Autodesk Fusion 360 part; units mm, degrees
(part 2 of 8)
extrude "Diffuser open rear skirt" add sketch "Diffuser hollow skirt outside profile" against normal blind 2.6 bodies 4
ref_plane "WorkPlane13" through (12.125, -2.4482, 27.9828) normal (0, -0.087156, 0.996195) x (1, 0, 0)
sketch "Diffuser optical cavity profile" plane through (0, -2.4482, 27.9828) normal (0, -0.087156, 0.996195) x (1, 0, 0)
  line L0 (7.7, 94.1972) -> (72.3, 94.1972)
  line L1 (72.3, 94.1972) -> (72.3, 101.7972)
  line L2 (72.3, 101.7972) -> (7.7, 101.7972)
  line L3 (7.7, 101.7972) -> (7.7, 94.1972)
  dimension "d533" = 7.7
  dimension "d534" = 94.1972
  dimension "d535" = 64.6
  dimension "d536" = 7.6
  constraint horizontal L0
  constraint vertical L1
  constraint horizontal L2
  constraint vertical L3
  measures "d533" horizontal distance of origin L0.start
  measures "d534" vertical distance of origin L0.start
  measures "d535" distance of L0.start L0.end
  measures "d536" distance of L0.end L1.end
extrude "Hollow diffuser from inside" cut sketch "Diffuser optical cavity profile" against normal blind 7 bodies 4
sketch "Diffuser right wire exit profile" plane through (0, -2.2216, 25.3927) normal (0, -0.087156, 0.996195) x (1, 0, 0)
  line L0 (71.5, 95.9972) -> (76.5, 95.9972)
  line L1 (76.5, 95.9972) -> (76.5, 99.9972)
  line L2 (76.5, 99.9972) -> (71.5, 99.9972)
  line L3 (71.5, 99.9972) -> (71.5, 95.9972)
  dimension "d539" = 71.5
  dimension "d540" = 95.9972
  dimension "d541" = 5
  dimension "d542" = 4
  constraint horizontal L0
  constraint vertical L1
  constraint horizontal L2
  constraint vertical L3
  measures "d539" horizontal distance of origin L0.start
  measures "d540" vertical distance of origin L0.start
  measures "d541" distance of L0.start L0.end
  measures "d542" distance of L0.end L1.end
extrude "Diffuser right wire exit" cut sketch "Diffuser right wire exit profile" against normal blind 6 bodies 4
sketch "Deep diffuser skirt clearance profile" plane through (0, -2.2739, 25.9904) normal (0, -0.087156, 0.996195) x (1, 0, 0)
  line L0 (5, 91.4972) -> (75, 91.4972)
  line L1 (75, 91.4972) -> (75, 104.4972)
  line L2 (75, 104.4972) -> (5, 104.4972)
  line L3 (5, 104.4972) -> (5, 91.4972)
  dimension "d545" = 5
  dimension "d546" = 91.4972
  dimension "d547" = 70
  dimension "d548" = 13
  constraint horizontal L0
  constraint vertical L1
  constraint horizontal L2
  constraint vertical L3
  measures "d545" horizontal distance of origin L0.start
  measures "d546" vertical distance of origin L0.start
  measures "d547" distance of L0.start L0.end
  measures "d548" distance of L0.end L1.end
extrude "Clear carrier around hollow diffuser" cut sketch "Deep diffuser skirt clearance profile" against normal blind 3.4 bodies 2
sketch "LED rear support web profile" plane through (0, -2.2739, 25.9904) normal (0, -0.087156, 0.996195) x (1, 0, 0)
  line L0 (6.3, 108.1799) -> (73.7, 108.1799)
  line L1 (73.7, 108.1799) -> (73.7, 112.1799)
  line L2 (73.7, 112.1799) -> (6.3, 112.1799)
  line L3 (6.3, 112.1799) -> (6.3, 108.1799)
  dimension "d551" = 6.3
  dimension "d552" = 108.1799
  dimension "d553" = 67.4
  dimension "d554" = 4
  constraint horizontal L0
  constraint vertical L1
  constraint horizontal L2
  constraint vertical L3
  measures "d551" horizontal distance of origin L0.start
  measures "d552" vertical distance of origin L0.start
  measures "d553" distance of L0.start L0.end
  measures "d554" distance of L0.end L1.end
extrude "LED rear support web" add sketch "LED rear support web profile" against normal blind 5.8 bodies 2
ref_plane "WorkPlane14" through (12.125, -1.9775, 22.6033) normal (0, -0.087156, 0.996195) x (1, 0, 0)
sketch "Continuous LED tray profile" plane through (0, -1.9775, 22.6033) normal (0, -0.087156, 0.996195) x (1, 0, 0)
  line L0 (6.3, 92.7972) -> (73.7, 92.7972)
  line L1 (73.7, 92.7972) -> (73.7, 114.4037)
  line L2 (73.7, 114.4037) -> (6.3, 114.4037)
  line L3 (6.3, 114.4037) -> (6.3, 92.7972)
  dimension "d559" = 6.3
  dimension "d560" = 92.7972
  dimension "d561" = 67.4
  dimension "d562" = 21.6065
  constraint horizontal L0
  constraint vertical L1
  constraint horizontal L2
  constraint vertical L3
  measures "d559" horizontal distance of origin L0.start
  measures "d560" vertical distance of origin L0.start
  measures "d561" distance of L0.start L0.end
  measures "d562" distance of L0.end L1.end
extrude "Continuous LED mounting crossbar" add sketch "Continuous LED tray profile" against normal blind 2.4 bodies 2
sketch "LED tray right wire relief profile" plane through (0, -1.9775, 22.6033) normal (0, -0.087156, 0.996195) x (1, 0, 0)
  line L0 (71.5, 95.9972) -> (75.5, 95.9972)
  line L1 (75.5, 95.9972) -> (75.5, 99.9972)
  line L2 (75.5, 99.9972) -> (71.5, 99.9972)
  line L3 (71.5, 99.9972) -> (71.5, 95.9972)
  dimension "d565" = 71.5
  dimension "d566" = 95.9972
  dimension "d567" = 4
  dimension "d568" = 4
  constraint horizontal L0
  constraint vertical L1
  constraint horizontal L2
  constraint vertical L3
  measures "d565" horizontal distance of origin L0.start
  measures "d566" vertical distance of origin L0.start
  measures "d567" distance of L0.start L0.end
  measures "d568" distance of L0.end L1.end
extrude "LED tray right wire relief" cut sketch "LED tray right wire relief profile" against normal blind 3.4 bodies 2
sketch "OLED seat 1 profile" plane through (0, -2.5179, 28.7797) normal (0, -0.087156, 0.996195) x (1, 0, 0)
  line L0 (5.75, 59.4972) -> (41.75, 59.4972)
  line L1 (41.75, 59.4972) -> (41.75, 62.4972)
  line L2 (41.75, 62.4972) -> (5.75, 62.4972)
  line L3 (5.75, 62.4972) -> (5.75, 59.4972)
  dimension "d571" = 5.75
  dimension "d572" = 59.4972
  dimension "d573" = 36
  dimension "d574" = 3
  constraint horizontal L0
  constraint vertical L1
  constraint horizontal L2
  constraint vertical L3
  measures "d571" horizontal distance of origin L0.start
  measures "d572" vertical distance of origin L0.start
  measures "d573" distance of L0.start L0.end
  measures "d574" distance of L0.end L1.end
extrude "OLED opposed locating ledge 1" add sketch "OLED seat 1 profile" against normal blind 2.8 bodies 1
sketch "OLED seat 2 profile" plane through (0, -2.5179, 28.7797) normal (0, -0.087156, 0.996195) x (1, 0, 0)
  line L0 (5.75, 88.4972) -> (41.75, 88.4972)
  line L1 (41.75, 88.4972) -> (41.75, 91.4972)
  line L2 (41.75, 91.4972) -> (5.75, 91.4972)
  line L3 (5.75, 91.4972) -> (5.75, 88.4972)
  dimension "d577" = 5.75
  dimension "d578" = 88.4972
  dimension "d579" = 36
  dimension "d580" = 3
  constraint horizontal L0
  constraint vertical L1
  constraint horizontal L2
  constraint vertical L3
  measures "d577" horizontal distance of origin L0.start
  measures "d578" vertical distance of origin L0.start
  measures "d579" distance of L0.start L0.end
  measures "d580" distance of L0.end L1.end
extrude "OLED opposed locating ledge 2" add sketch "OLED seat 2 profile" against normal blind 2.8 bodies 1
sketch "OLED PCB carrier clearance profile" plane through (0, -2.2739, 25.9904) normal (0, -0.087156, 0.996195) x (1, 0, 0)
  line L0 (5.55, 59.2972) -> (41.95, 59.2972)
  line L1 (41.95, 59.2972) -> (41.95, 93.6972)
  line L2 (41.95, 93.6972) -> (5.55, 93.6972)
  line L3 (5.55, 93.6972) -> (5.55, 59.2972)
  dimension "d583" = 5.55
  dimension "d584" = 59.2972
  dimension "d585" = 36.4
  dimension "d586" = 34.4
  constraint horizontal L0
  constraint vertical L1
  constraint horizontal L2
  constraint vertical L3
  measures "d583" horizontal distance of origin L0.start
  measures "d584" vertical distance of origin L0.start
  measures "d585" distance of L0.start L0.end
  measures "d586" distance of L0.end L1.end
extrude "OLED PCB clearance in carrier" cut sketch "OLED PCB carrier clearance profile" against normal blind 1.8 bodies 2
ref_plane "WorkPlane15" through (12.125, -2.117, 24.1972) normal (0, -0.087156, 0.996195) x (1, 0, 0)
sketch "OLED front clamp root profile" plane through (0, -2.2739, 25.9904) normal (0, -0.087156, 0.996195) x (1, 0, 0)
  line L0 (18, 58.4972) -> (32, 58.4972)
  line L1 (32, 58.4972) -> (32, 59.4972)
  line L2 (32, 59.4972) -> (18, 59.4972)
  line L3 (18, 59.4972) -> (18, 58.4972)
  dimension "d591" = 18
  dimension "d592" = 58.4972
  dimension "d593" = 14
  dimension "d594" = 1
  constraint horizontal L0
  constraint vertical L1
  constraint horizontal L2
  constraint vertical L3
  measures "d591" horizontal distance of origin L0.start
  measures "d592" vertical distance of origin L0.start
  measures "d593" distance of L0.start L0.end
  measures "d594" distance of L0.end L1.end
extrude "OLED front clamp root" add sketch "OLED front clamp root profile" against normal blind 3.8 bodies 2
sketch "OLED front opposed clamp profile" plane through (0, -2.117, 24.1972) normal (0, -0.087156, 0.996195) x (1, 0, 0)
  line L0 (18, 58.4972) -> (32, 58.4972)
  line L1 (32, 58.4972) -> (32, 62.4972)
  line L2 (32, 62.4972) -> (18, 62.4972)
  line L3 (18, 62.4972) -> (18, 58.4972)
  dimension "d597" = 18
  dimension "d598" = 58.4972
  dimension "d599" = 14
  dimension "d600" = 4
  constraint horizontal L0
  constraint vertical L1
  constraint horizontal L2
  constraint vertical L3
  measures "d597" horizontal distance of origin L0.start
  measures "d598" vertical distance of origin L0.start
  measures "d599" distance of L0.start L0.end
  measures "d600" distance of L0.end L1.end
extrude "OLED front opposed clamp" add sketch "OLED front opposed clamp profile" against normal blind 2 bodies 2
sketch "OLED rear clamp connecting bridge profile" plane through (0, -1.9775, 22.6033) normal (0, -0.087156, 0.996195) x (1, 0, 0)
  line L0 (18, 89.2972) -> (32, 89.2972)
  line L1 (32, 89.2972) -> (32, 93.0972)
  line L2 (32, 93.0972) -> (18, 93.0972)
  line L3 (18, 93.0972) -> (18, 89.2972)
  dimension "d603" = 18
  dimension "d604" = 89.2972
  dimension "d605" = 14
  dimension "d606" = 3.8
  constraint horizontal L0
  constraint vertical L1
  constraint horizontal L2
  constraint vertical L3
  measures "d603" horizontal distance of origin L0.start
  measures "d604" vertical distance of origin L0.start
  measures "d605" distance of L0.start L0.end
  measures "d606" distance of L0.end L1.end
extrude "OLED rear clamp connecting bridge" add sketch "OLED rear clamp connecting bridge profile" against normal blind 2.4 bodies 2
sketch "OLED rear opposed clamp profile" plane through (0, -2.117, 24.1972) normal (0, -0.087156, 0.996195) x (1, 0, 0)
  line L0 (18, 89.4972) -> (32, 89.4972)
  line L1 (32, 89.4972) -> (32, 91.4972)
  line L2 (32, 91.4972) -> (18, 91.4972)
  line L3 (18, 91.4972) -> (18, 89.4972)
  dimension "d609" = 18
  dimension "d610" = 89.4972
  dimension "d611" = 14
  dimension "d612" = 2
  constraint horizontal L0
  constraint vertical L1
  constraint horizontal L2
  constraint vertical L3
  measures "d609" horizontal distance of origin L0.start
  measures "d610" vertical distance of origin L0.start
  measures "d611" distance of L0.start L0.end
  measures "d612" distance of L0.end L1.end
extrude "OLED rear opposed clamp" add sketch "OLED rear opposed clamp profile" against normal blind 2 bodies 2
sketch "OLED PCB carrier clearance profile (1)" plane through (0, -2.2739, 25.9904) normal (0, -0.087156, 0.996195) x (1, 0, 0)
  line L0 (5.55, 59.2972) -> (41.95, 59.2972)
  line L1 (41.95, 59.2972) -> (41.95, 93.6972)
  line L2 (41.95, 93.6972) -> (5.55, 93.6972)
  line L3 (5.55, 93.6972) -> (5.55, 59.2972)
  dimension "d615" = 5.55
  dimension "d616" = 59.2972
  dimension "d617" = 36.4
  dimension "d618" = 34.4
  constraint horizontal L0
  constraint vertical L1
  constraint horizontal L2
  constraint vertical L3
  measures "d615" horizontal distance of origin L0.start
  measures "d616" vertical distance of origin L0.start
  measures "d617" distance of L0.start L0.end
  measures "d618" distance of L0.end L1.end
extrude "OLED PCB clearance in carrier (1)" cut sketch "OLED PCB carrier clearance profile (1)" against normal blind 1.8 bodies 2
ref_plane "WorkPlane16" through (0, 0, 26.3) normal (0, 0, 1) x (1, 0, 0)
sketch "PCB1 perimeter support profile" plane through (0, 0, 26.3) normal (0, 0, 1) x (1, 0, 0)
  line L0 (3.2, 62.2) -> (4.8, 62.2)
  line L1 (4.8, 62.2) -> (4.8, 66.2)
  line L2 (4.8, 66.2) -> (3.2, 66.2)
  line L3 (3.2, 66.2) -> (3.2, 62.2)
  dimension "d623" = 3.2
  dimension "d624" = 62.2
  dimension "d625" = 1.6
  dimension "d626" = 4
  constraint horizontal L0
  constraint vertical L1
  constraint horizontal L2
  constraint vertical L3
  measures "d623" horizontal distance of origin L0.start
  measures "d624" vertical distance of origin L0.start
  measures "d625" distance of L0.start L0.end
  measures "d626" distance of L0.end L1.end
sketch "PCB1 short post bridge profile" plane through (0, 0, 26.3) normal (0, 0, 1) x (1, 0, 0)
  line L0 (3.2, 62.2) -> (7, 62.2)
  line L1 (7, 62.2) -> (7, 66.2)
  line L2 (7, 66.2) -> (3.2, 66.2)
  line L3 (3.2, 66.2) -> (3.2, 62.2)
  dimension "d629" = 3.2
  dimension "d630" = 62.2
  dimension "d631" = 3.8
  dimension "d632" = 4
  constraint horizontal L0
  constraint vertical L1
  constraint horizontal L2
  constraint vertical L3
  measures "d629" horizontal distance of origin L0.start
  measures "d630" vertical distance of origin L0.start
  measures "d631" distance of L0.start L0.end
  measures "d632" distance of L0.end L1.end
sketch "PCB1 post profile" plane through (0, 0, 22.3) normal (0, 0, 1) x (1, 0, 0)
  circle A0 centre (7, 64.2) radius 2.2
  dimension "d635" = 7
  dimension "d636" = 64.2
  dimension "d637" = 4.4
  measures "d635" horizontal distance of origin A0.centre
  measures "d636" vertical distance of origin A0.centre
  measures "d637" diameter of A0
sketch "PCB1 M2 pilot profile" plane through (0, 0, 22.3) normal (0, 0, 1) x (1, 0, 0)
  circle A0 centre (7, 64.2) radius 0.85
  dimension "d640" = 7
  dimension "d641" = 64.2
  dimension "d642" = 1.7
  measures "d640" horizontal distance of origin A0.centre
  measures "d641" vertical distance of origin A0.centre
  measures "d642" diameter of A0
sketch "PCB2 perimeter support profile" plane through (0, 0, 26.3) normal (0, 0, 1) x (1, 0, 0)
  line L0 (75.2, 62.2) -> (76.8, 62.2)
  line L1 (76.8, 62.2) -> (76.8, 66.2)
  line L2 (76.8, 66.2) -> (75.2, 66.2)
  line L3 (75.2, 66.2) -> (75.2, 62.2)
  dimension "d645" = 75.2
  dimension "d646" = 62.2
  dimension "d647" = 1.6
  dimension "d648" = 4
  constraint horizontal L0
  constraint vertical L1
  constraint horizontal L2
  constraint vertical L3
  measures "d645" horizontal distance of origin L0.start
  measures "d646" vertical distance of origin L0.start
  measures "d647" distance of L0.start L0.end
  measures "d648" distance of L0.end L1.end
sketch "PCB2 short post bridge profile" plane through (0, 0, 26.3) normal (0, 0, 1) x (1, 0, 0)
  line L0 (73, 62.2) -> (76.8, 62.2)
  line L1 (76.8, 62.2) -> (76.8, 66.2)
  line L2 (76.8, 66.2) -> (73, 66.2)
  line L3 (73, 66.2) -> (73, 62.2)
  dimension "d651" = 73
  dimension "d652" = 62.2
  dimension "d653" = 3.8
  dimension "d654" = 4
  constraint horizontal L0
  constraint vertical L1
  constraint horizontal L2
  constraint vertical L3
  measures "d651" horizontal distance of origin L0.start
  measures "d652" vertical distance of origin L0.start
  measures "d653" distance of L0.start L0.end
  measures "d654" distance of L0.end L1.end
sketch "PCB2 post profile" plane through (0, 0, 22.3) normal (0, 0, 1) x (1, 0, 0)
  circle A0 centre (73, 64.2) radius 2.2
  dimension "d657" = 73
  dimension "d658" = 64.2
  dimension "d659" = 4.4
  measures "d657" horizontal distance of origin A0.centre
  measures "d658" vertical distance of origin A0.centre
  measures "d659" diameter of A0
sketch "PCB2 M2 pilot profile" plane through (0, 0, 22.3) normal (0, 0, 1) x (1, 0, 0)
  circle A0 centre (73, 64.2) radius 0.85
  dimension "d662" = 73
  dimension "d663" = 64.2
  dimension "d664" = 1.7
  measures "d662" horizontal distance of origin A0.centre
  measures "d663" vertical distance of origin A0.centre
  measures "d664" diameter of A0
sketch "PCB3 perimeter support profile" plane through (0, 0, 26.3) normal (0, 0, 1) x (1, 0, 0)
  line L0 (3.2, 108.2) -> (4.8, 108.2)
  line L1 (4.8, 108.2) -> (4.8, 112.2)
  line L2 (4.8, 112.2) -> (3.2, 112.2)
  line L3 (3.2, 112.2) -> (3.2, 108.2)
  dimension "d667" = 3.2
  dimension "d668" = 108.2
  dimension "d669" = 1.6
  dimension "d670" = 4
  constraint horizontal L0
  constraint vertical L1
  constraint horizontal L2
  constraint vertical L3
  measures "d667" horizontal distance of origin L0.start
  measures "d668" vertical distance of origin L0.start
  measures "d669" distance of L0.start L0.end
  measures "d670" distance of L0.end L1.end
sketch "PCB3 short post bridge profile" plane through (0, 0, 26.3) normal (0, 0, 1) x (1, 0, 0)
  line L0 (3.2, 108.2) -> (7, 108.2)
  line L1 (7, 108.2) -> (7, 112.2)
  line L2 (7, 112.2) -> (3.2, 112.2)
  line L3 (3.2, 112.2) -> (3.2, 108.2)
  dimension "d673" = 3.2
  dimension "d674" = 108.2
  dimension "d675" = 3.8
  dimension "d676" = 4
  constraint horizontal L0
  constraint vertical L1
  constraint horizontal L2
  constraint vertical L3
  measures "d673" horizontal distance of origin L0.start
  measures "d674" vertical distance of origin L0.start
  measures "d675" distance of L0.start L0.end
  measures "d676" distance of L0.end L1.end
sketch "PCB3 post profile" plane through (0, 0, 22.3) normal (0, 0, 1) x (1, 0, 0)
  circle A0 centre (7, 110.2) radius 2.2
  dimension "d679" = 7
  dimension "d680" = 110.2
  dimension "d681" = 4.4
  measures "d679" horizontal distance of origin A0.centre
  measures "d680" vertical distance of origin A0.centre
  measures "d681" diameter of A0
sketch "PCB3 M2 pilot profile" plane through (0, 0, 22.3) normal (0, 0, 1) x (1, 0, 0)
  circle A0 centre (7, 110.2) radius 0.85
  dimension "d684" = 7
  dimension "d685" = 110.2
  dimension "d686" = 1.7
  measures "d684" horizontal distance of origin A0.centre
  measures "d685" vertical distance of origin A0.centre
  measures "d686" diameter of A0
sketch "PCB4 perimeter support profile" plane through (0, 0, 26.3) normal (0, 0, 1) x (1, 0, 0)
  line L0 (75.2, 108.2) -> (76.8, 108.2)
  line L1 (76.8, 108.2) -> (76.8, 112.2)
  line L2 (76.8, 112.2) -> (75.2, 112.2)
  line L3 (75.2, 112.2) -> (75.2, 108.2)
  dimension "d689" = 75.2
  dimension "d690" = 108.2
  dimension "d691" = 1.6
  dimension "d692" = 4
  constraint horizontal L0
  constraint vertical L1
  constraint horizontal L2
  constraint vertical L3
  measures "d689" horizontal distance of origin L0.start
  measures "d690" vertical distance of origin L0.start
  measures "d691" distance of L0.start L0.end
  measures "d692" distance of L0.end L1.end
sketch "PCB4 short post bridge profile" plane through (0, 0, 26.3) normal (0, 0, 1) x (1, 0, 0)
  line L0 (73, 108.2) -> (76.8, 108.2)
  line L1 (76.8, 108.2) -> (76.8, 112.2)
  line L2 (76.8, 112.2) -> (73, 112.2)
  line L3 (73, 112.2) -> (73, 108.2)
  dimension "d695" = 73
  dimension "d696" = 108.2
  dimension "d697" = 3.8
  dimension "d698" = 4
  constraint horizontal L0
  constraint vertical L1
  constraint horizontal L2
  constraint vertical L3
  measures "d695" horizontal distance of origin L0.start
  measures "d696" vertical distance of origin L0.start
  measures "d697" distance of L0.start L0.end
  measures "d698" distance of L0.end L1.end
sketch "PCB4 post profile" plane through (0, 0, 22.3) normal (0, 0, 1) x (1, 0, 0)
  circle A0 centre (73, 110.2) radius 2.2
  dimension "d701" = 73
  dimension "d702" = 110.2
  dimension "d703" = 4.4
  measures "d701" horizontal distance of origin A0.centre
  measures "d702" vertical distance of origin A0.centre
  measures "d703" diameter of A0
sketch "PCB4 M2 pilot profile" plane through (0, 0, 22.3) normal (0, 0, 1) x (1, 0, 0)
  circle A0 centre (73, 110.2) radius 0.85
  dimension "d706" = 73
  dimension "d707" = 110.2
  dimension "d708" = 1.7
  measures "d706" horizontal distance of origin A0.centre
  measures "d707" vertical distance of origin A0.centre
  measures "d708" diameter of A0
ref_plane "WorkPlane17" through (12.125, -1.8381, 21.0094) normal (0, -0.087156, 0.996195) x (1, 0, 0)
sketch "M1 carrier stop profile" plane through (0, -1.8729, 21.4079) normal (0, -0.087156, 0.996195) x (1, 0, 0)
  circle A0 centre (12, 13.0275) radius 3.5
  dimension "d713" = 12
  dimension "d715" = 7
  measures "d713" horizontal distance of origin A0.centre
  measures "d715" diameter of A0
extrude "M1 rigid carrier stop" add sketch "M1 carrier stop profile" against normal blind 0.4 bodies 1
sketch "M1 stop insert entry profile" plane through (0, -1.8381, 21.0094) normal (0, -0.087156, 0.996195) x (1, 0, 0)
  circle A0 centre (12, 13.0275) radius 1.6
  dimension "d718" = 12
  dimension "d720" = 3.2
  measures "d718" horizontal distance of origin A0.centre
  measures "d720" diameter of A0
extrude "M1 open stop insert entry" cut sketch "M1 stop insert entry profile" along normal blind 0.5 bodies 1
sketch "M2 carrier stop profile" plane through (0, -1.8729, 21.4079) normal (0, -0.087156, 0.996195) x (1, 0, 0)
  circle A0 centre (68, 13.0275) radius 3.5
  dimension "d723" = 68
  dimension "d725" = 7
  measures "d723" horizontal distance of origin A0.centre
  measures "d725" diameter of A0
extrude "M2 rigid carrier stop" add sketch "M2 carrier stop profile" against normal blind 0.4 bodies 1
sketch "M2 stop insert entry profile" plane through (0, -1.8381, 21.0094) normal (0, -0.087156, 0.996195) x (1, 0, 0)
  circle A0 centre (68, 13.0275) radius 1.6
  dimension "d728" = 68
  dimension "d730" = 3.2
  measures "d728" horizontal distance of origin A0.centre
  measures "d730" diameter of A0
extrude "M2 open stop insert entry" cut sketch "M2 stop insert entry profile" along normal blind 0.5 bodies 1
sketch "M3 carrier stop profile" plane through (0, -1.8729, 21.4079) normal (0, -0.087156, 0.996195) x (1, 0, 0)
  circle A0 centre (12, 108.3268) radius 3.5
  dimension "d733" = 12
  dimension "d735" = 7
  measures "d733" horizontal distance of origin A0.centre
  measures "d735" diameter of A0
extrude "M3 rigid carrier stop" add sketch "M3 carrier stop profile" against normal blind 0.4 bodies 1
sketch "M3 stop insert entry profile" plane through (0, -1.8381, 21.0094) normal (0, -0.087156, 0.996195) x (1, 0, 0)
  circle A0 centre (12, 108.3268) radius 1.6
  dimension "d738" = 12
  dimension "d740" = 3.2
  measures "d738" horizontal distance of origin A0.centre
  measures "d740" diameter of A0
extrude "M3 open stop insert entry" cut sketch "M3 stop insert entry profile" along normal blind 0.5 bodies 1
sketch "M3 restored carrier pocket profile" plane through (0, -1.8381, 21.0094) normal (0, -0.087156, 0.996195) x (1, 0, 0)
  circle A0 centre (12, 108.3268) radius 4.2024
  dimension "d743" = 12
  dimension "d745" = 8.4049
  measures "d743" horizontal distance of origin A0.centre
  measures "d745" diameter of A0
extrude "M3 restored carrier pocket" cut sketch "M3 restored carrier pocket profile" along normal blind 7.8 bodies 2
sketch "M3 restored screw clearance profile" plane through (0, -2.2739, 25.9904) normal (0, -0.087156, 0.996195) x (1, 0, 0)
  circle A0 centre (12, 108.3268) radius 1.15
  dimension "d748" = 12
  dimension "d750" = 2.3
  measures "d748" horizontal distance of origin A0.centre
  measures "d750" diameter of A0
extrude "M3 restored screw clearance" cut sketch "M3 restored screw clearance profile" against normal blind 10 bodies 2
sketch "M3 restored cover boss relief profile" plane through (0, 0, 2) normal (0, 0, 1) x (1, 0, 0)
  circle A0 centre (20, 112) radius 3.2
  dimension "d753" = 20
  dimension "d754" = 112
  dimension "d755" = 6.4
  measures "d753" horizontal distance of origin A0.centre
  measures "d754" vertical distance of origin A0.centre
  measures "d755" diameter of A0
extrude "M3 restored cover boss relief" cut sketch "M3 restored cover boss relief profile" along normal blind 40.0612 bodies 2
sketch "M4 carrier stop profile" plane through (0, -1.8729, 21.4079) normal (0, -0.087156, 0.996195) x (1, 0, 0)
  circle A0 centre (68, 108.3268) radius 3.5
  dimension "d758" = 68
  dimension "d760" = 7
  measures "d758" horizontal distance of origin A0.centre
  measures "d760" diameter of A0
extrude "M4 rigid carrier stop" add sketch "M4 carrier stop profile" against normal blind 0.4 bodies 1
sketch "M4 stop insert entry profile" plane through (0, -1.8381, 21.0094) normal (0, -0.087156, 0.996195) x (1, 0, 0)
  circle A0 centre (68, 108.3268) radius 1.6
  dimension "d763" = 68
  dimension "d765" = 3.2
  measures "d763" horizontal distance of origin A0.centre
  measures "d765" diameter of A0
extrude "M4 open stop insert entry" cut sketch "M4 stop insert entry profile" along normal blind 0.5 bodies 1
sketch "M4 restored carrier pocket profile" plane through (0, -1.8381, 21.0094) normal (0, -0.087156, 0.996195) x (1, 0, 0)
  circle A0 centre (68, 108.3268) radius 4.2024
  dimension "d768" = 68
  dimension "d770" = 8.4049
  measures "d768" horizontal distance of origin A0.centre
  measures "d770" diameter of A0
extrude "M4 restored carrier pocket" cut sketch "M4 restored carrier pocket profile" along normal blind 7.8 bodies 2
sketch "M4 restored screw clearance profile" plane through (0, -2.2739, 25.9904) normal (0, -0.087156, 0.996195) x (1, 0, 0)
  circle A0 centre (68, 108.3268) radius 1.15
  dimension "d773" = 68
  dimension "d775" = 2.3
  measures "d773" horizontal distance of origin A0.centre
  measures "d775" diameter of A0
extrude "M4 restored screw clearance" cut sketch "M4 restored screw clearance profile" against normal blind 10 bodies 2
sketch "M4 restored cover boss relief profile" plane through (0, 0, 2) normal (0, 0, 1) x (1, 0, 0)
  circle A0 centre (60, 112) radius 3.2
  dimension "d778" = 60
  dimension "d779" = 112
  dimension "d780" = 6.4
  measures "d778" horizontal distance of origin A0.centre
  measures "d779" vertical distance of origin A0.centre
  measures "d780" diameter of A0
extrude "M4 restored cover boss relief" cut sketch "M4 restored cover boss relief profile" along normal blind 40.0612 bodies 2
ref_plane "WorkPlane18" through (3.2, 0, 0) normal (1, 0, 0) x (0, 1, 0)
sketch "PCB direct rail 1 profile" plane through (3.2, 0, 0) normal (1, 0, 0) x (0, 0, -1)
  line L0 (-27.8, 62.2) -> (-27.8, 112.2)
  line L1 (-27.8, 112.2) -> (-34.8009, 112.2)
  line L2 (-34.8009, 112.2) -> (-30.4265, 62.2)
  line L3 (-30.4265, 62.2) -> (-27.8, 62.2)
  dimension "d788" = 27.8
  dimension "d789" = 62.2
  dimension "d790" = 50
  dimension "d791" = 7.0009
  dimension "d792" = 2.6265
  constraint vertical L0
  constraint horizontal L1
  constraint horizontal L3
  measures "d788" horizontal distance of origin L0.start
  measures "d789" vertical distance of origin L0.start
  measures "d790" distance of L0.start L0.end
  measures "d791" distance of L0.end L1.end
  measures "d792" distance of L0.start L2.end
extrude "PCB direct rail 1" add sketch "PCB direct rail 1 profile" along normal blind 1.6 bodies 2
ref_plane "WorkPlane19" through (75.2, 0, 0) normal (1, 0, 0) x (0, 1, 0)
sketch "PCB direct rail 2 profile" plane through (75.2, 0, 0) normal (1, 0, 0) x (0, 0, -1)
  line L0 (-27.8, 62.2) -> (-27.8, 112.2)
  line L1 (-27.8, 112.2) -> (-34.8009, 112.2)
  line L2 (-34.8009, 112.2) -> (-30.4265, 62.2)
  line L3 (-30.4265, 62.2) -> (-27.8, 62.2)
  dimension "d797" = 27.8
  dimension "d798" = 62.2
  dimension "d799" = 50
  dimension "d800" = 7.0009
  dimension "d801" = 2.6265
  constraint vertical L0
  constraint horizontal L1
  constraint horizontal L3
  measures "d797" horizontal distance of origin L0.start
  measures "d798" vertical distance of origin L0.start
  measures "d799" distance of L0.start L0.end
  measures "d800" distance of L0.end L1.end
  measures "d801" distance of L0.start L2.end
extrude "PCB direct rail 2" add sketch "PCB direct rail 2 profile" along normal blind 1.6 bodies 2
ref_plane "WorkPlane20" through (0, 0, 27.8) normal (0, 0, 1) x (1, 0, 0)
sketch "PCB direct mount 1 ear profile" plane through (0, 0, 27.8) normal (0, 0, 1) x (1, 0, 0)
  line L0 (3.2, 62) -> (9.2, 62)
  line L1 (9.2, 62) -> (9.2, 66.4)
  line L2 (9.2, 66.4) -> (3.2, 66.4)
  line L3 (3.2, 66.4) -> (3.2, 62)
  dimension "d806" = 3.2
  dimension "d807" = 62
  dimension "d808" = 6
  dimension "d809" = 4.4
  constraint horizontal L0
  constraint vertical L1
  constraint horizontal L2
  constraint vertical L3
  measures "d806" horizontal distance of origin L0.start
  measures "d807" vertical distance of origin L0.start
  measures "d808" distance of L0.start L0.end
  measures "d809" distance of L0.end L1.end
extrude "PCB direct mount 1 ear" add sketch "PCB direct mount 1 ear profile" along normal blind 1.5 bodies 2
sketch "PCB direct mount 1 boss profile" plane through (0, 0, 22.3) normal (0, 0, 1) x (1, 0, 0)
  circle A0 centre (7, 64.2) radius 2.2
  dimension "d812" = 7
  dimension "d813" = 64.2
  dimension "d814" = 4.4
  measures "d812" horizontal distance of origin A0.centre
  measures "d813" vertical distance of origin A0.centre
  measures "d814" diameter of A0
extrude "PCB direct mount 1 boss" add sketch "PCB direct mount 1 boss profile" along normal blind 7 bodies 2
sketch "PCB direct mount 1 screw profile" plane through (0, 0, 22.3) normal (0, 0, 1) x (1, 0, 0)
  circle A0 centre (7, 64.2) radius 0.85
  dimension "d817" = 7
  dimension "d818" = 64.2
  dimension "d819" = 1.7
  measures "d817" horizontal distance of origin A0.centre
  measures "d818" vertical distance of origin A0.centre
  measures "d819" diameter of A0
extrude "PCB direct mount 1 screw pilot" cut sketch "PCB direct mount 1 screw profile" along normal blind 4.5 bodies 2
sketch "PCB direct mount 2 ear profile" plane through (0, 0, 27.8) normal (0, 0, 1) x (1, 0, 0)
  line L0 (70.8, 62) -> (76.8, 62)
  line L1 (76.8, 62) -> (76.8, 66.4)
  line L2 (76.8, 66.4) -> (70.8, 66.4)
  line L3 (70.8, 66.4) -> (70.8, 62)
  dimension "d822" = 70.8
  dimension "d823" = 62
  dimension "d824" = 6
  dimension "d825" = 4.4
  constraint horizontal L0
  constraint vertical L1
  constraint horizontal L2
  constraint vertical L3
  measures "d822" horizontal distance of origin L0.start
  measures "d823" vertical distance of origin L0.start
  measures "d824" distance of L0.start L0.end
  measures "d825" distance of L0.end L1.end
extrude "PCB direct mount 2 ear" add sketch "PCB direct mount 2 ear profile" along normal blind 1.5 bodies 2
sketch "PCB direct mount 2 boss profile" plane through (0, 0, 22.3) normal (0, 0, 1) x (1, 0, 0)
  circle A0 centre (73, 64.2) radius 2.2
  dimension "d828" = 73
  dimension "d829" = 64.2
  dimension "d830" = 4.4
  measures "d828" horizontal distance of origin A0.centre
  measures "d829" vertical distance of origin A0.centre
  measures "d830" diameter of A0
extrude "PCB direct mount 2 boss" add sketch "PCB direct mount 2 boss profile" along normal blind 7 bodies 2
sketch "PCB direct mount 2 screw profile" plane through (0, 0, 22.3) normal (0, 0, 1) x (1, 0, 0)
  circle A0 centre (73, 64.2) radius 0.85
  dimension "d833" = 73
  dimension "d834" = 64.2
  dimension "d835" = 1.7
  measures "d833" horizontal distance of origin A0.centre
  measures "d834" vertical distance of origin A0.centre
  measures "d835" diameter of A0
extrude "PCB direct mount 2 screw pilot" cut sketch "PCB direct mount 2 screw profile" along normal blind 4.5 bodies 2
sketch "PCB direct mount 3 ear profile" plane through (0, 0, 27.8) normal (0, 0, 1) x (1, 0, 0)
  line L0 (3.2, 108) -> (9.2, 108)
  line L1 (9.2, 108) -> (9.2, 112.4)
  line L2 (9.2, 112.4) -> (3.2, 112.4)
  line L3 (3.2, 112.4) -> (3.2, 108)
  dimension "d838" = 3.2
  dimension "d839" = 108
  dimension "d840" = 6
  dimension "d841" = 4.4
  constraint horizontal L0
  constraint vertical L1
  constraint horizontal L2
  constraint vertical L3
  measures "d838" horizontal distance of origin L0.start
  measures "d839" vertical distance of origin L0.start
  measures "d840" distance of L0.start L0.end
  measures "d841" distance of L0.end L1.end
extrude "PCB direct mount 3 ear" add sketch "PCB direct mount 3 ear profile" along normal blind 1.5 bodies 2
sketch "PCB direct mount 3 boss profile" plane through (0, 0, 22.3) normal (0, 0, 1) x (1, 0, 0)
  circle A0 centre (7, 110.2) radius 2.2
  dimension "d844" = 7
  dimension "d845" = 110.2
  dimension "d846" = 4.4
  measures "d844" horizontal distance of origin A0.centre
  measures "d845" vertical distance of origin A0.centre
  measures "d846" diameter of A0
extrude "PCB direct mount 3 boss" add sketch "PCB direct mount 3 boss profile" along normal blind 7 bodies 2
sketch "PCB direct mount 3 screw profile" plane through (0, 0, 22.3) normal (0, 0, 1) x (1, 0, 0)
  circle A0 centre (7, 110.2) radius 0.85
  dimension "d849" = 7
  dimension "d850" = 110.2
  dimension "d851" = 1.7
  measures "d849" horizontal distance of origin A0.centre
  measures "d850" vertical distance of origin A0.centre
  measures "d851" diameter of A0
extrude "PCB direct mount 3 screw pilot" cut sketch "PCB direct mount 3 screw profile" along normal blind 4.5 bodies 2
sketch "PCB direct mount 4 ear profile" plane through (0, 0, 27.8) normal (0, 0, 1) x (1, 0, 0)
  line L0 (70.8, 108) -> (76.8, 108)
  line L1 (76.8, 108) -> (76.8, 112.4)
  line L2 (76.8, 112.4) -> (70.8, 112.4)
  line L3 (70.8, 112.4) -> (70.8, 108)
  dimension "d854" = 70.8
  dimension "d855" = 108
  dimension "d856" = 6
  dimension "d857" = 4.4
  constraint horizontal L0
  constraint vertical L1
  constraint horizontal L2
  constraint vertical L3
  measures "d854" horizontal distance of origin L0.start
  measures "d855" vertical distance of origin L0.start
  measures "d856" distance of L0.start L0.end
  measures "d857" distance of L0.end L1.end
extrude "PCB direct mount 4 ear" add sketch "PCB direct mount 4 ear profile" along normal blind 1.5 bodies 2
sketch "PCB direct mount 4 boss profile" plane through (0, 0, 22.3) normal (0, 0, 1) x (1, 0, 0)
  circle A0 centre (73, 110.2) radius 2.2
  dimension "d860" = 73
  dimension "d861" = 110.2
  dimension "d862" = 4.4
  measures "d860" horizontal distance of origin A0.centre
  measures "d861" vertical distance of origin A0.centre
  measures "d862" diameter of A0
extrude "PCB direct mount 4 boss" add sketch "PCB direct mount 4 boss profile" along normal blind 7 bodies 2
sketch "PCB direct mount 4 screw profile" plane through (0, 0, 22.3) normal (0, 0, 1) x (1, 0, 0)
  circle A0 centre (73, 110.2) radius 0.85
  dimension "d865" = 73
  dimension "d866" = 110.2
  dimension "d867" = 1.7
  measures "d865" horizontal distance of origin A0.centre
  measures "d866" vertical distance of origin A0.centre
  measures "d867" diameter of A0
extrude "PCB direct mount 4 screw pilot" cut sketch "PCB direct mount 4 screw profile" along normal blind 4.5 bodies 2
ref_plane "WorkPlane28" through (12.125, -2.1431, 24.4961) normal (0, -0.087156, 0.996195) x (1, 0, 0)
ref_plane "WorkPlane29" through (12.125, -1.6638, 19.017) normal (0, -0.087156, 0.996195) x (1, 0, 0)
ref_plane "WorkPlane30" through (12.125, -1.2106, 13.8368) normal (0, -0.087156, 0.996195) x (1, 0, 0)
ref_plane "WorkPlane31" through (12.125, -2.056, 23.4999) normal (0, -0.087156, 0.996195) x (1, 0, 0)
ref_plane "WorkPlane32" through (12.125, -1.1931, 13.6376) normal (0, -0.087156, 0.996195) x (1, 0, 0)
ref_plane "WorkPlane33" through (0, 0, 2) normal (0, 0, 1) x (1, 0, 0)
sketch "SW1 receiver profile" plane through (0, -2.1431, 24.4961) normal (0, -0.087156, 0.996195) x (1, 0, 0)
  line L0 (6.3, 17.6972) -> (24.7, 17.6972)
  line L1 (24.7, 17.6972) -> (24.7, 35.2972)
  line L2 (24.7, 35.2972) -> (6.3, 35.2972)
  line L3 (6.3, 35.2972) -> (6.3, 17.6972)
  dimension "d1846" = 6.3
  dimension "d1847" = 17.6972
  dimension "d1848" = 18.4
  dimension "d1849" = 17.6
  constraint horizontal L0
  constraint vertical L1
  constraint horizontal L2
  constraint vertical L3
  measures "d1846" horizontal distance of origin L0.start
  measures "d1847" vertical distance of origin L0.start
  measures "d1848" distance of L0.start L0.end
  measures "d1849" distance of L0.end L1.end
extrude "SW1 integrated receiver" add sketch "SW1 receiver profile" against normal blind 11.5 bodies 2
sketch "SW1 switch lower clearance profile" plane through (0, -2.1431, 24.4961) normal (0, -0.087156, 0.996195) x (1, 0, 0)
  line L0 (7.5, 18.4972) -> (23.5, 18.4972)
  line L1 (23.5, 18.4972) -> (23.5, 34.4972)
  line L2 (23.5, 34.4972) -> (7.5, 34.4972)
  line L3 (7.5, 34.4972) -> (7.5, 18.4972)
  dimension "d1852" = 7.5
  dimension "d1853" = 18.4972
  dimension "d1854" = 16
  dimension "d1855" = 16
  constraint horizontal L0
  constraint vertical L1
  constraint horizontal L2
  constraint vertical L3
  measures "d1852" horizontal distance of origin L0.start
  measures "d1853" vertical distance of origin L0.start
  measures "d1854" distance of L0.start L0.end
  measures "d1855" distance of L0.end L1.end
extrude "SW1 switch lower clearance" cut sketch "SW1 switch lower clearance profile" against normal blind 5.5 bodies 2
sketch "SW1 holder pocket profile" plane through (0, -1.6638, 19.017) normal (0, -0.087156, 0.996195) x (1, 0, 0)
  line L0 (9.874, 19.925) -> (21.3055, 19.925)
  line L1 (21.3055, 19.925) -> (21.3055, 30.0741)
  line L2 (21.3055, 30.0741) -> (9.874, 30.0741)
  line L3 (9.874, 30.0741) -> (9.874, 19.925)
  dimension "d1858" = 9.874
  dimension "d1859" = 19.925
  dimension "d1860" = 11.4315
  dimension "d1861" = 10.1491
  constraint horizontal L0
  constraint vertical L1
  constraint horizontal L2
  constraint vertical L3
  measures "d1858" horizontal distance of origin L0.start
  measures "d1859" vertical distance of origin L0.start
  measures "d1860" distance of L0.start L0.end
  measures "d1861" distance of L0.end L1.end
extrude "SW1 open-bottom holder pocket" cut sketch "SW1 holder pocket profile" against normal blind 6.2 bodies 2
sketch "SW1 spring 1 release 1 profile" plane through (0, -2.056, 23.4999) normal (0, -0.087156, 0.996195) x (1, 0, 0)
  line L0 (6.2897, 27.0995) -> (9.874, 27.0995)
  line L1 (9.874, 27.0995) -> (9.874, 27.6995)
  line L2 (9.874, 27.6995) -> (6.2897, 27.6995)
  line L3 (6.2897, 27.6995) -> (6.2897, 27.0995)
  dimension "d1864" = 6.2897
  dimension "d1865" = 27.0995
  dimension "d1866" = 3.5843
  dimension "d1867" = 0.6
  constraint horizontal L0
  constraint vertical L1
  constraint horizontal L2
  constraint vertical L3
  measures "d1864" horizontal distance of origin L0.start
  measures "d1865" vertical distance of origin L0.start
  measures "d1866" distance of L0.start L0.end
  measures "d1867" distance of L0.end L1.end
extrude "SW1 spring 1 release 1" cut sketch "SW1 spring 1 release 1 profile" against normal blind 10.7 bodies 2
sketch "SW1 spring 1 release 2 profile" plane through (0, -2.056, 23.4999) normal (0, -0.087156, 0.996195) x (1, 0, 0)
  line L0 (6.2897, 29.6995) -> (9.874, 29.6995)
  line L1 (9.874, 29.6995) -> (9.874, 30.2995)
  line L2 (9.874, 30.2995) -> (6.2897, 30.2995)
  line L3 (6.2897, 30.2995) -> (6.2897, 29.6995)
  dimension "d1870" = 6.2897
  dimension "d1871" = 29.6995
  dimension "d1872" = 3.5843
  dimension "d1873" = 0.6
  constraint horizontal L0
  constraint vertical L1
  constraint horizontal L2
  constraint vertical L3
  measures "d1870" horizontal distance of origin L0.start
  measures "d1871" vertical distance of origin L0.start
  measures "d1872" distance of L0.start L0.end
  measures "d1873" distance of L0.end L1.end
extrude "SW1 spring 1 release 2" cut sketch "SW1 spring 1 release 2 profile" against normal blind 10.7 bodies 2
sketch "SW1 spring 1 inner clearance profile" plane through (0, -1.6638, 19.017) normal (0, -0.087156, 0.996195) x (1, 0, 0)
  line L0 (7.1897, 27.6995) -> (9.874, 27.6995)
  line L1 (9.874, 27.6995) -> (9.874, 29.6995)
  line L2 (9.874, 29.6995) -> (7.1897, 29.6995)
  line L3 (7.1897, 29.6995) -> (7.1897, 27.6995)
  dimension "d1876" = 7.1897
  dimension "d1877" = 27.6995
  dimension "d1878" = 2.6843
  dimension "d1879" = 2
  constraint horizontal L0
  constraint vertical L1
  constraint horizontal L2
  constraint vertical L3
  measures "d1876" horizontal distance of origin L0.start
  measures "d1877" vertical distance of origin L0.start
  measures "d1878" distance of L0.start L0.end
  measures "d1879" distance of L0.end L1.end
extrude "SW1 spring 1 inner clearance" cut sketch "SW1 spring 1 inner clearance profile" against normal blind 6.2 bodies 2
sketch "SW1 spring 1 hook profile" plane through (0, -1.2106, 13.8368) normal (0, -0.087156, 0.996195) x (1, 0, 0)
  line L0 (6.3897, 27.6995) -> (10.374, 27.6995)
  line L1 (10.374, 27.6995) -> (10.374, 29.6995)
  line L2 (10.374, 29.6995) -> (6.3897, 29.6995)
  line L3 (6.3897, 29.6995) -> (6.3897, 27.6995)
  dimension "d1882" = 6.3897
  dimension "d1883" = 27.6995
  dimension "d1884" = 3.9843
  dimension "d1885" = 2
  constraint horizontal L0
  constraint vertical L1
  constraint horizontal L2
  constraint vertical L3
  measures "d1882" horizontal distance of origin L0.start
  measures "d1883" vertical distance of origin L0.start
  measures "d1884" distance of L0.start L0.end
  measures "d1885" distance of L0.end L1.end
extrude "SW1 spring 1 retaining hook" add sketch "SW1 spring 1 hook profile" against normal blind 0.8 bodies 2
chamfer "SW1 spring 1 45 degree lead-in" distance 0.35 angle 45 1 edges at (10.374, 27.4495, 15.5412) tangent chain off on bodies 2
sketch "SW1 spring 2 release 1 profile" plane through (0, -2.056, 23.4999) normal (0, -0.087156, 0.996195) x (1, 0, 0)
  line L0 (21.3055, 27.0995) -> (24.8897, 27.0995)
  line L1 (24.8897, 27.0995) -> (24.8897, 27.6995)
  line L2 (24.8897, 27.6995) -> (21.3055, 27.6995)
  line L3 (21.3055, 27.6995) -> (21.3055, 27.0995)
  dimension "d1889" = 21.3055
  dimension "d1890" = 27.0995
  dimension "d1891" = 3.5843
  dimension "d1892" = 0.6
  constraint horizontal L0
  constraint vertical L1
  constraint horizontal L2
  constraint vertical L3
  measures "d1889" horizontal distance of origin L0.start
  measures "d1890" vertical distance of origin L0.start
  measures "d1891" distance of L0.start L0.end
  measures "d1892" distance of L0.end L1.end
extrude "SW1 spring 2 release 1" cut sketch "SW1 spring 2 release 1 profile" against normal blind 10.7 bodies 2
sketch "SW1 spring 2 release 2 profile" plane through (0, -2.056, 23.4999) normal (0, -0.087156, 0.996195) x (1, 0, 0)
  line L0 (21.3055, 29.6995) -> (24.8897, 29.6995)
  line L1 (24.8897, 29.6995) -> (24.8897, 30.2995)
  line L2 (24.8897, 30.2995) -> (21.3055, 30.2995)
  line L3 (21.3055, 30.2995) -> (21.3055, 29.6995)
  dimension "d1895" = 21.3055
  dimension "d1896" = 29.6995
  dimension "d1897" = 3.5843
  dimension "d1898" = 0.6
  constraint horizontal L0
  constraint vertical L1
  constraint horizontal L2
  constraint vertical L3
  measures "d1895" horizontal distance of origin L0.start
  measures "d1896" vertical distance of origin L0.start
  measures "d1897" distance of L0.start L0.end
  measures "d1898" distance of L0.end L1.end
extrude "SW1 spring 2 release 2" cut sketch "SW1 spring 2 release 2 profile" against normal blind 10.7 bodies 2
sketch "SW1 spring 2 inner clearance profile" plane through (0, -1.6638, 19.017) normal (0, -0.087156, 0.996195) x (1, 0, 0)
  line L0 (21.3055, 27.6995) -> (23.9897, 27.6995)
  line L1 (23.9897, 27.6995) -> (23.9897, 29.6995)
  line L2 (23.9897, 29.6995) -> (21.3055, 29.6995)
  line L3 (21.3055, 29.6995) -> (21.3055, 27.6995)
  dimension "d1901" = 21.3055
  dimension "d1902" = 27.6995
  dimension "d1903" = 2.6843
  dimension "d1904" = 2
  constraint horizontal L0
  constraint vertical L1
  constraint horizontal L2
  constraint vertical L3
  measures "d1901" horizontal distance of origin L0.start
  measures "d1902" vertical distance of origin L0.start
  measures "d1903" distance of L0.start L0.end
  measures "d1904" distance of L0.end L1.end
extrude "SW1 spring 2 inner clearance" cut sketch "SW1 spring 2 inner clearance profile" against normal blind 6.2 bodies 2
sketch "SW1 spring 2 hook profile" plane through (0, -1.2106, 13.8368) normal (0, -0.087156, 0.996195) x (1, 0, 0)
  line L0 (20.8055, 27.6995) -> (24.7897, 27.6995)
  line L1 (24.7897, 27.6995) -> (24.7897, 29.6995)
  line L2 (24.7897, 29.6995) -> (20.8055, 29.6995)
  line L3 (20.8055, 29.6995) -> (20.8055, 27.6995)
  dimension "d1907" = 20.8055
  dimension "d1908" = 27.6995
  dimension "d1909" = 3.9843
  dimension "d1910" = 2
  constraint horizontal L0
  constraint vertical L1
  constraint horizontal L2
  constraint vertical L3
  measures "d1907" horizontal distance of origin L0.start
  measures "d1908" vertical distance of origin L0.start
  measures "d1909" distance of L0.start L0.end
  measures "d1910" distance of L0.end L1.end
extrude "SW1 spring 2 retaining hook" add sketch "SW1 spring 2 hook profile" against normal blind 0.8 bodies 2
chamfer "SW1 spring 2 45 degree lead-in" distance 0.35 angle 45 1 edges at (20.8055, 27.4495, 15.5412) tangent chain off on bodies 2
sketch "SW1 upper stop 1 profile" plane through (0, -1.6638, 19.017) normal (0, -0.087156, 0.996195) x (1, 0, 0)
  line L0 (12.0897, 28.9995) -> (13.0897, 28.9995)
  line L1 (13.0897, 28.9995) -> (13.0897, 33.7995)
  line L2 (13.0897, 33.7995) -> (12.0897, 33.7995)
  line L3 (12.0897, 33.7995) -> (12.0897, 28.9995)
  dimension "d1914" = 12.0897
  dimension "d1915" = 28.9995
  dimension "d1916" = 1
  dimension "d1917" = 4.8
  constraint horizontal L0
  constraint vertical L1
  constraint horizontal L2
  constraint vertical L3
  measures "d1914" horizontal distance of origin L0.start
  measures "d1915" vertical distance of origin L0.start
  measures "d1916" distance of L0.start L0.end
  measures "d1917" distance of L0.end L1.end
extrude "SW1 upper stop 1" add sketch "SW1 upper stop 1 profile" along normal blind 0.8 bodies 2
sketch "SW1 upper stop 2 profile" plane through (0, -1.6638, 19.017) normal (0, -0.087156, 0.996195) x (1, 0, 0)
  line L0 (18.0897, 28.9995) -> (19.0897, 28.9995)
  line L1 (19.0897, 28.9995) -> (19.0897, 33.7995)
  line L2 (19.0897, 33.7995) -> (18.0897, 33.7995)
  line L3 (18.0897, 33.7995) -> (18.0897, 28.9995)
  dimension "d1920" = 18.0897
  dimension "d1921" = 28.9995
  dimension "d1922" = 1
  dimension "d1923" = 4.8
  constraint horizontal L0
  constraint vertical L1
  constraint horizontal L2
  constraint vertical L3
  measures "d1920" horizontal distance of origin L0.start
  measures "d1921" vertical distance of origin L0.start
  measures "d1922" distance of L0.start L0.end
  measures "d1923" distance of L0.end L1.end
extrude "SW1 upper stop 2" add sketch "SW1 upper stop 2 profile" along normal blind 0.8 bodies 2
ref_plane "WorkPlane34" through (12.125, -1.5592, 17.8216) normal (0, -0.087156, 0.996195) x (1, 0, 0)
sketch "SW1 wire exit 1 profile" plane through (0, -1.5592, 17.8216) normal (0, -0.087156, 0.996195) x (1, 0, 0)
  line L0 (6.2897, 19.8995) -> (10.074, 19.8995)
  line L1 (10.074, 19.8995) -> (10.074, 27.6995)
  line L2 (10.074, 27.6995) -> (6.2897, 27.6995)
  line L3 (6.2897, 27.6995) -> (6.2897, 19.8995)
  dimension "d1928" = 6.2897
  dimension "d1929" = 19.8995
  dimension "d1930" = 3.7843
  dimension "d1931" = 7.8
  constraint horizontal L0
  constraint vertical L1
  constraint horizontal L2
  constraint vertical L3
  measures "d1928" horizontal distance of origin L0.start
  measures "d1929" vertical distance of origin L0.start
  measures "d1930" distance of L0.start L0.end
  measures "d1931" distance of L0.end L1.end
extrude "SW1 wire exit 1" cut sketch "SW1 wire exit 1 profile" against normal blind 5 bodies 2
sketch "SW1 wire exit 2 profile" plane through (0, -1.5592, 17.8216) normal (0, -0.087156, 0.996195) x (1, 0, 0)
  line L0 (21.1055, 19.8995) -> (24.8897, 19.8995)
  line L1 (24.8897, 19.8995) -> (24.8897, 27.6995)
  line L2 (24.8897, 27.6995) -> (21.1055, 27.6995)
  line L3 (21.1055, 27.6995) -> (21.1055, 19.8995)
  dimension "d1934" = 21.1055
  dimension "d1935" = 19.8995
  dimension "d1936" = 3.7843
  dimension "d1937" = 7.8
  constraint horizontal L0
  constraint vertical L1
  constraint horizontal L2
  constraint vertical L3
  measures "d1934" horizontal distance of origin L0.start
  measures "d1935" vertical distance of origin L0.start
  measures "d1936" distance of L0.start L0.end
  measures "d1937" distance of L0.end L1.end
extrude "SW1 wire exit 2" cut sketch "SW1 wire exit 2 profile" against normal blind 5 bodies 2
sketch "SW1 support 1 reinforced stem profile" plane through (0, 0, 2) normal (0, 0, 1) x (1, 0, 0)
  line L0 (11.8897, 20.0158) -> (14.2897, 20.0158)
  line L1 (14.2897, 20.0158) -> (14.2897, 25.0158)
  line L2 (14.2897, 25.0158) -> (11.8897, 25.0158)
  line L3 (11.8897, 25.0158) -> (11.8897, 20.0158)
  dimension "d1940" = 11.8897
  dimension "d1941" = 20.0158
  dimension "d1942" = 2.4
  dimension "d1943" = 5
  constraint horizontal L0
  constraint vertical L1
  constraint horizontal L2
  constraint vertical L3
  measures "d1940" horizontal distance of origin L0.start
  measures "d1941" vertical distance of origin L0.start
  measures "d1942" distance of L0.start L0.end
  measures "d1943" distance of L0.end L1.end
extrude "SW1 support 1 reinforced stem" add sketch "SW1 support 1 reinforced stem profile" along normal blind 11.7118 bodies 3